smart-dial (Autodesk Fusion 360 design; units mm, degrees)
Autodesk Fusion 360 part; units mm, degrees
sketch "base outline" plane through (0, 0, 0) normal (0, 0, 1) x (1, 0, 0)
  circle A0 centre (0, 0) radius 33
  dimension "d17" = 66
  measures "d17" diameter of A0
extrude "Extrude1" add sketch "base outline" along normal blind 8.75 makes body 1
ref_plane "WorkPlane1" through (0, 0, 8.75) normal (0, 0, 1) x (1, 0, 0)
sketch "knob outline" plane through (0, 0, 8.75) normal (0, 0, 1) x (1, 0, 0)
  circle A0 centre (0, 0) radius 33
  dimension "d22" = 66
  measures "d22" diameter of A0
extrude "Extrude2" add sketch "knob outline" along normal blind 13.25 separate body makes body 2
ref_plane "WorkPlane2" through (0, 0, 22) normal (0, 0, 1) x (1, 0, 0)
sketch "knob bore" plane through (0, 0, 22) normal (0, 0, 1) x (1, 0, 0)
  circle A0 centre (0, 0) radius 28.1
  dimension "d27" = 56.2
  measures "d27" diameter of A0
extrude "Extrude3" cut sketch "knob bore" along normal mid plane 26.5 bodies 2
ref_plane "WorkPlane3" through (0, 0, 8.75) normal (0, 0, 1) x (1, 0, 0)
sketch "chassis outline" plane through (0, 0, 8.75) normal (0, 0, 1) x (1, 0, 0)
  circle A0 centre (0, 0) radius 28.1
  dimension "d32" = 56.2
  measures "d32" diameter of A0
extrude "Extrude4" add sketch "chassis outline" along normal blind 13.25 separate body makes body 3
ref_plane "WorkPlane4" through (0, 0, 22) normal (0, 0, 1) x (1, 0, 0)
sketch "glass pocket" plane through (0, 0, 22) normal (0, 0, 1) x (1, 0, 0)
  circle A0 centre (0, 0) radius 28
  dimension "d37" = 56
  measures "d37" diameter of A0
extrude "Extrude5" cut sketch "glass pocket" along normal mid plane 4 bodies 3
sketch "cover glass" plane through (0, 0, 22) normal (0, 0, 1) x (1, 0, 0)
  circle A0 centre (0, 0) radius 28
  dimension "d40" = 56
  measures "d40" diameter of A0
extrude "Extrude6" add sketch "cover glass" against normal blind 2 separate body makes body 4
sketch "active display area" plane through (0, 0, 22) normal (0, 0, 1) x (1, 0, 0)
  circle A0 centre (0, 0) radius 23.5
  dimension "d43" = 47
  measures "d43" diameter of A0
chamfer "Chamfer knob top outer" distance 0.4 distance2 0.15 1 edges at (-30.7668, -11.9333, 22) measured on face at (31.1392, -3.0355, 22) tangent chain off on bodies 2
ref_plane "WorkPlane47" through (0, 0, 7.25) normal (0, 0, 1) x (1, 0, 0)
sketch "flute sec 00" plane through (0, 0, 7.25) normal (0, 0, 1) x (1, 0, 0)
  line L0 (-3.4494, -32.8192) -> (3.4494, -32.8192)
  line L1 (3.4494, -32.8192) -> (3.4494, -38)
  line L2 (3.4494, -38) -> (-3.4494, -38)
  line L3 (-3.4494, -38) -> (-3.4494, -32.8192)
ref_plane "WorkPlane48" through (0, 0, 8.2656) normal (0, 0, 1) x (1, 0, 0)
sketch "flute sec 01" plane through (0, 0, 8.2656) normal (0, 0, 1) x (1, 0, 0)
  line L0 (-2.6582, -32.8928) -> (4.2387, -32.7267)
  line L1 (4.2387, -32.7267) -> (4.3634, -37.9059)
  line L2 (4.3634, -37.9059) -> (-2.5335, -38.072)
  line L3 (-2.5335, -38.072) -> (-2.6582, -32.8928)
ref_plane "WorkPlane49" through (0, 0, 9.2812) normal (0, 0, 1) x (1, 0, 0)
sketch "flute sec 02" plane through (0, 0, 9.2812) normal (0, 0, 1) x (1, 0, 0)
  line L0 (-1.8654, -32.9472) -> (5.0254, -32.6151)
  line L1 (5.0254, -32.6151) -> (5.2749, -37.7899)
  line L2 (5.2749, -37.7899) -> (-1.616, -38.122)
  line L3 (-1.616, -38.122) -> (-1.8654, -32.9472)
ref_plane "WorkPlane50" through (0, 0, 10.2969) normal (0, 0, 1) x (1, 0, 0)
sketch "flute sec 03" plane through (0, 0, 10.2969) normal (0, 0, 1) x (1, 0, 0)
  line L0 (-1.0716, -32.9826) -> (5.8093, -32.4846)
  line L1 (5.8093, -32.4846) -> (6.1832, -37.6519)
  line L2 (6.1832, -37.6519) -> (-0.6976, -38.1499)
  line L3 (-0.6976, -38.1499) -> (-1.0716, -32.9826)
ref_plane "WorkPlane51" through (0, 0, 11.3125) normal (0, 0, 1) x (1, 0, 0)
sketch "flute sec 04" plane through (0, 0, 11.3125) normal (0, 0, 1) x (1, 0, 0)
  line L0 (-0.2771, -32.9988) -> (6.5898, -32.3353)
  line L1 (6.5898, -32.3353) -> (7.088, -37.4921)
  line L2 (7.088, -37.4921) -> (0.2211, -38.1556)
  line L3 (0.2211, -38.1556) -> (-0.2771, -32.9988)
ref_plane "WorkPlane52" through (0, 0, 12.3281) normal (0, 0, 1) x (1, 0, 0)
sketch "flute sec 05" plane through (0, 0, 12.3281) normal (0, 0, 1) x (1, 0, 0)
  line L0 (0.5175, -32.9959) -> (7.3665, -32.1673)
  line L1 (7.3665, -32.1673) -> (7.9887, -37.3106)
  line L2 (7.9887, -37.3106) -> (1.1398, -38.1392)
  line L3 (1.1398, -38.1392) -> (0.5175, -32.9959)
ref_plane "WorkPlane53" through (0, 0, 13.3438) normal (0, 0, 1) x (1, 0, 0)
sketch "flute sec 06" plane through (0, 0, 13.3438) normal (0, 0, 1) x (1, 0, 0)
  line L0 (1.3119, -32.9739) -> (8.1389, -31.9806)
  line L1 (8.1389, -31.9806) -> (8.8848, -37.1074)
  line L2 (8.8848, -37.1074) -> (2.0578, -38.1007)
  line L3 (2.0578, -38.1007) -> (1.3119, -32.9739)
ref_plane "WorkPlane54" through (0, 0, 14.3594) normal (0, 0, 1) x (1, 0, 0)
sketch "flute sec 07" plane through (0, 0, 14.3594) normal (0, 0, 1) x (1, 0, 0)
  line L0 (2.1054, -32.9328) -> (8.9065, -31.7754)
  line L1 (8.9065, -31.7754) -> (9.7757, -36.8827)
  line L2 (9.7757, -36.8827) -> (2.9746, -38.0401)
  line L3 (2.9746, -38.0401) -> (2.1054, -32.9328)
ref_plane "WorkPlane55" through (0, 0, 15.375) normal (0, 0, 1) x (1, 0, 0)
sketch "flute sec 08" plane through (0, 0, 15.375) normal (0, 0, 1) x (1, 0, 0)
  line L0 (2.8978, -32.8725) -> (9.669, -31.5517)
  line L1 (9.669, -31.5517) -> (10.6609, -36.6366)
  line L2 (10.6609, -36.6366) -> (3.8897, -37.9575)
  line L3 (3.8897, -37.9575) -> (2.8978, -32.8725)
ref_plane "WorkPlane56" through (0, 0, 16.3906) normal (0, 0, 1) x (1, 0, 0)
sketch "flute sec 09" plane through (0, 0, 16.3906) normal (0, 0, 1) x (1, 0, 0)
  line L0 (3.6885, -32.7932) -> (10.426, -31.3097)
  line L1 (10.426, -31.3097) -> (11.54, -36.3693)
  line L2 (11.54, -36.3693) -> (4.8025, -37.8528)
  line L3 (4.8025, -37.8528) -> (3.6885, -32.7932)
ref_plane "WorkPlane57" through (0, 0, 17.4062) normal (0, 0, 1) x (1, 0, 0)
sketch "flute sec 10" plane through (0, 0, 17.4062) normal (0, 0, 1) x (1, 0, 0)
  line L0 (4.477, -32.6949) -> (11.1768, -31.0496)
  line L1 (11.1768, -31.0496) -> (12.4124, -36.0809)
  line L2 (12.4124, -36.0809) -> (5.7125, -37.7262)
  line L3 (5.7125, -37.7262) -> (4.477, -32.6949)
ref_plane "WorkPlane58" through (0, 0, 18.4219) normal (0, 0, 1) x (1, 0, 0)
sketch "flute sec 11" plane through (0, 0, 18.4219) normal (0, 0, 1) x (1, 0, 0)
  line L0 (5.2629, -32.5776) -> (11.9212, -30.7715)
  line L1 (11.9212, -30.7715) -> (13.2775, -35.7716)
  line L2 (13.2775, -35.7716) -> (6.6193, -37.5777)
  line L3 (6.6193, -37.5777) -> (5.2629, -32.5776)
ref_plane "WorkPlane59" through (0, 0, 19.4375) normal (0, 0, 1) x (1, 0, 0)
sketch "flute sec 12" plane through (0, 0, 19.4375) normal (0, 0, 1) x (1, 0, 0)
  line L0 (6.0458, -32.4415) -> (12.6587, -30.4755)
  line L1 (12.6587, -30.4755) -> (14.135, -35.4415)
  line L2 (14.135, -35.4415) -> (7.5222, -37.4074)
  line L3 (7.5222, -37.4074) -> (6.0458, -32.4415)
ref_plane "WorkPlane60" through (0, 0, 20.4531) normal (0, 0, 1) x (1, 0, 0)
sketch "flute sec 13" plane through (0, 0, 20.4531) normal (0, 0, 1) x (1, 0, 0)
  line L0 (6.8252, -32.2865) -> (13.3888, -30.1619)
  line L1 (13.3888, -30.1619) -> (14.9843, -35.0909)
  line L2 (14.9843, -35.0909) -> (8.4207, -37.2155)
  line L3 (8.4207, -37.2155) -> (6.8252, -32.2865)
ref_plane "WorkPlane61" through (0, 0, 21.4688) normal (0, 0, 1) x (1, 0, 0)
sketch "flute sec 14" plane through (0, 0, 21.4688) normal (0, 0, 1) x (1, 0, 0)
  line L0 (7.6006, -32.1128) -> (14.1112, -29.8308)
  line L1 (14.1112, -29.8308) -> (15.8249, -34.7199)
  line L2 (15.8249, -34.7199) -> (9.3143, -37.0019)
  line L3 (9.3143, -37.0019) -> (7.6006, -32.1128)
ref_plane "WorkPlane62" through (0, 0, 22.4844) normal (0, 0, 1) x (1, 0, 0)
sketch "flute sec 15" plane through (0, 0, 22.4844) normal (0, 0, 1) x (1, 0, 0)
  line L0 (8.3716, -31.9205) -> (14.8253, -29.4824)
  line L1 (14.8253, -29.4824) -> (16.6563, -34.3288)
  line L2 (16.6563, -34.3288) -> (10.2026, -36.7669)
  line L3 (10.2026, -36.7669) -> (8.3716, -31.9205)
ref_plane "WorkPlane63" through (0, 0, 23.5) normal (0, 0, 1) x (1, 0, 0)
sketch "flute sec 16" plane through (0, 0, 23.5) normal (0, 0, 1) x (1, 0, 0)
  line L0 (9.1378, -31.7096) -> (15.5309, -29.1168)
  line L1 (15.5309, -29.1168) -> (17.478, -33.9178)
  line L2 (17.478, -33.9178) -> (11.0849, -36.5106)
  line L3 (11.0849, -36.5106) -> (9.1378, -31.7096)
loft "Flute cutter" add profiles "flute sec 00", "flute sec 01", "flute sec 02", "flute sec 03", "flute sec 04", "flute sec 05", "flute sec 06", "flute sec 07", "flute sec 08", "flute sec 09", "flute sec 10", "flute sec 11", "flute sec 12", "flute sec 13", "flute sec 14", "flute sec 15", "flute sec 16" section 1 section 2 section 3 section 4 section 5 section 6 section 7 section 8 section 9 section 10 section 11 section 12 section 13 section 14 section 15 section 16 section 17 separate body makes body 5
pattern_circular "Flutes around" count 30 over 360 about axis through (0, 0, 1.75) along (0, 0, 1) of bodies 5 makes body 6 at (19.5252, -32.6204, 19.8889) makes body 7 at (25.8807, -27.848, 19.8889) makes body 8 at (31.105, -21.8586, 19.8889) makes body 9 at (34.97, -14.9138, 19.8889) makes body 10 at (37.3066, -7.3173, 19.8889) makes body 11 at (38.0127, 0.5991, 19.8889) makes body 12 at (37.6477, 5.2892, 16.2778) makes body 13 at (35.7253, 13.001, 16.2778) makes body 14 at (30.4007, 22.828, 19.8889) makes body 15 at (24.9902, 28.6498, 19.8889) makes body 16 at (18.4875, 33.2195, 19.8889) makes body 17 at (11.1768, 36.3373, 19.8889) makes body 18 at (5.6609, 37.5936, 19.8889) makes body 19 at (-4.5692, 37.7418, 19.8889) makes body 20 at (-9.1955, 36.8885, 16.2778) makes body 21 at (-19.5252, 32.6204, 19.8889) makes body 22 at (-25.8807, 27.848, 19.8889) makes body 23 at (-31.105, 21.8586, 19.8889) makes body 24 at (-34.97, 14.9138, 19.8889) makes body 25 at (-36.7959, 9.5595, 19.8889) makes body 26 at (-38.0127, -0.5991, 19.8889) makes body 27 at (-37.0574, -8.4893, 19.8889) makes body 28 at (-34.4826, -16.0085, 19.8889) makes body 29 at (-30.4007, -22.828, 19.8889) makes body 30 at (-24.9902, -28.6498, 19.8889) makes body 31 at (-18.4875, -33.2195, 19.8889) makes body 32 at (-11.1768, -36.3373, 19.8889) makes body 33 at (-3.3776, -37.8671, 19.8889) makes body 34 at (4.5692, -37.7418, 19.8889)
combine "Cut flutes" operation cut target body 2 tool bodies 5 6 7 8 9 10 11 12 13 14 15 16 17 18 19 20 21 22 23 24 25 26 27 28 29 30 31 32 33 34 5
split_face "Split screen from bezel" 1 faces at (9.2788, 5.1402, 22) by curves path "active display area" along A0 on bodies 4
ref_plane "WorkPlane69" through (0, -33, 0) normal (0, 1, 0) x (0, 0, 1)
sketch "Reset pinhole" plane through (0, -33, 0) normal (0, 1, 0) x (1, 0, 0)
  circle A0 centre (0, -4.375) radius 0.8
extrude "Extrude49" add sketch "Reset pinhole" along normal blind 4 separate body makes body 35
move_body "Move42" bodies 35 to x (0.770513, -0.637424, 0) y (0.637424, 0.770513, 0) z (0, 0, 1) at (0, 0, 0)
sketch "USB-C" plane through (0, -33, 0) normal (0, 1, 0) x (1, 0, 0)
  line L0 (-3.05, -2.725) -> (3.05, -2.725)
  line L1 (-3.05, -6.025) -> (3.05, -6.025)
  arc A0 (3.05, -6.025) -> (3.05, -2.725) centre (3.05, -4.375) ccw
  arc A1 (-3.05, -2.725) -> (-3.05, -6.025) centre (-3.05, -4.375) ccw
extrude "Extrude50" add sketch "USB-C" along normal blind 7 separate body makes body 36
move_body "Move43" bodies 36 to x (0.951057, -0.309017, 0) y (0.309017, 0.951057, 0) z (0, 0, 1) at (0, 0, 0)
sketch "Headphone jack" plane through (0, -33, 0) normal (0, 1, 0) x (1, 0, 0)
  circle A0 centre (0, -4.375) radius 2.25
extrude "Extrude51" add sketch "Headphone jack" along normal blind 3 separate body makes body 37
move_body "Move44" bodies 37 to x (0.971134, 0.238533, 0) y (-0.238533, 0.971134, 0) z (0, 0, 1) at (0, 0, 0)
sketch "Toggle switch cutout" plane through (0, -33, 0) normal (0, 1, 0) x (1, 0, 0)
  line L0 (-2.7, -2.4) -> (2.7, -2.4)
  line L1 (-2.7, -5.5) -> (2.7, -5.5)
  line L2 (3.9, -4.3) -> (3.9, -3.6)
  line L3 (-3.9, -4.3) -> (-3.9, -3.6)
  arc A0 (3.9, -3.6) -> (2.7, -2.4) centre (2.7, -3.6) ccw
  arc A1 (2.7, -5.5) -> (3.9, -4.3) centre (2.7, -4.3) ccw
  arc A2 (-3.9, -4.3) -> (-2.7, -5.5) centre (-2.7, -4.3) ccw
  arc A3 (-2.7, -2.4) -> (-3.9, -3.6) centre (-2.7, -3.6) ccw
extrude "Extrude52" add sketch "Toggle switch cutout" along normal blind 1.2 separate body makes body 38
move_body "Move45" bodies 38 to x (0.802817, 0.596225, 0) y (-0.596225, 0.802817, 0) z (0, 0, 1) at (0, 0, 0)
combine "Cut base ports" operation cut target body 1 tool bodies 35 36 37 38
sketch "USB-C tongue" plane through (0, -33, 0) normal (0, 1, 0) x (1, 0, 0)
  line L0 (-3.05, -4.025) -> (3.05, -4.025)
  line L1 (-3.05, -4.725) -> (3.05, -4.725)
  arc A0 (3.05, -4.725) -> (3.05, -4.025) centre (3.05, -4.375) ccw
  arc A1 (-3.05, -4.025) -> (-3.05, -4.725) centre (-3.05, -4.375) ccw
extrude "Extrude53" add sketch "USB-C tongue" along normal blind 5.2 from surface at 1.3 separate body makes body 39
move_body "Move46" bodies 39 to x (0.951057, -0.309017, 0) y (0.309017, 0.951057, 0) z (0, 0, 1) at (0, 0, 0)
sketch "Toggle switch" plane through (0, -33, 0) normal (0, 1, 0) x (1, 0, 0)
  line L0 (0.1, -2.5) -> (2.7, -2.5)
  line L1 (0.1, -5.4) -> (2.7, -5.4)
  line L2 (3.8, -4.3) -> (3.8, -3.6)
  line L3 (-1, -4.3) -> (-1, -3.6)
  arc A0 (3.8, -3.6) -> (2.7, -2.5) centre (2.7, -3.6) ccw
  arc A1 (2.7, -5.4) -> (3.8, -4.3) centre (2.7, -4.3) ccw
  arc A2 (-1, -4.3) -> (0.1, -5.4) centre (0.1, -4.3) ccw
  arc A3 (0.1, -2.5) -> (-1, -3.6) centre (0.1, -3.6) ccw
extrude "Extrude54" add sketch "Toggle switch" along normal blind 1.3 from surface at -0.2 separate body makes body 40
move_body "Move47" bodies 40 to x (0.802817, 0.596225, 0) y (-0.596225, 0.802817, 0) z (0, 0, 1) at (0, 0, 0)
sketch "Base rim relief" plane through (0, 0, 0) normal (0, 0, 1) x (1, 0, 0)
  circle A0 centre (0, 0) radius 31.2
  circle A1 centre (0, 0) radius 35
  dimension "d372" = 62.4
  measures "d372" diameter of A0
extrude "Base rim relief (1)" cut sketch "Base rim relief" along normal blind 1 bodies 1
equation "dia_overall = 66 mm" comment "Outer diameter - READ from Waveshare outline drawing"
equation "h_overall = 22 mm" comment "Overall height - READ from Waveshare outline drawing"
equation "h_knob = 13.25 mm" comment "Blue knob height - MEASURED BY DARREN on the real dial"
equation "h_base = h_overall - h_knob" comment "Black base height = h_overall - h_knob"
equation "dia_base = dia_overall" comment "Base diameter - DARREN: flush with the flute tips, no overhang"
equation "dia_bore = dia_glass + 2 * glass_gap" comment "Knob opening = glass plus the 0.1 mm gap each side"
equation "dia_glass = 56 mm" comment "Cover glass diameter - MEASURED BY DARREN"
equation "dia_active = 47 mm" comment "Active screen area - MEASURED BY DARREN (black border 4.5 mm wide)"
equation "glass_recess = 0 mm" comment "DARREN: glass is flush with the top, no recess"
equation "t_glass = 2 mm" comment "Glass plus bezel stack thickness - GUESS"
equation "c_knob_top = 0.4 mm" comment "Top-edge chamfer: bite across the TOP face"
equation "flute_count = 30" comment "Flutes - COUNTED BY DARREN on the real dial"
equation "flute_depth = 0.1808 mm" comment "MINIMUM possible: flat facets, flute meets flute with no gap"
equation "flute_twist = 18 deg" comment "Twist of a flute over the knob height - measured off the Waveshare render"
equation "z_ports = h_base / 2" comment "Ports sit on the vertical midline of the black base - DARREN"
equation "d17 = dia_base"
equation "d18 = h_base"
equation "d20 = h_base"
equation "d22 = dia_overall"
equation "d23 = h_knob"
equation "d25 = h_overall"
equation "d27 = dia_bore"
equation "d28 = h_knob"
equation "d30 = h_base"
equation "d32 = dia_bore"
equation "d33 = h_knob - glass_recess"
equation "d35 = h_overall - glass_recess"
equation "d37 = dia_glass"
equation "d38 = t_glass"
equation "d40 = dia_glass"
equation "d41 = -t_glass"
equation "d43 = dia_active"
equation "d212 = flute_count"
equation "glass_gap = 0.1 mm" comment "Gap between the blue ring and the glass - DARREN"
equation "c_knob_side = 0.15 mm" comment "Top-edge chamfer: drop down the SIDE face"
equation "d224 = c_knob_top"
equation "d225 = c_knob_side"
equation "toggle_w = 7.8 mm" comment "Toggle cutout width"
equation "toggle_h = 2.9 mm + 2 * toggle_gap" comment "Cutout height = 2.9 mm button (CALIPERS) plus clearance each side"
equation "toggle_corner = 1.2 mm" comment "Toggle cutout corner radius - scaled with the new height to keep the same look"
equation "toggle_gap = 0.1 mm" comment "Clearance between the toggle and its cutout - DARREN"
equation "toggle_proud = 0.2 mm" comment "How far the toggle stands out of the base - DARREN"
equation "toggle_sw = 4.8 mm" comment "Toggle button width - CALIPERS"
equation "toggle_z = toggle_from_bottom + toggle_h / 2 - z_ports" comment "Derived: puts the cutout bottom toggle_from_bottom above the base bottom"
equation "toggle_from_bottom = 2.4 mm" comment "Bottom of the toggle cutout above the bottom of the base - CALIPERS"
equation "d348 = -dia_base / 2"
equation "foot_dia = 62.4 mm" comment "Central foot that drops into the mount recess - mount side is 62.6, 0.1 clearance each side"
equation "foot_step = 1 mm" comment "How far the outer rim is relieved - matches the 1 mm step in the Smart Dial v2 mount"
equation "d372 = foot_dia"
equation "d373 = foot_step"
named bodies: "Base (black)", "Knob (blue anodised)", "Chassis / bezel (black)", "Cover glass", "cutter Reset pinhole", "cutter USB-C", "cutter Headphone jack", "cutter Toggle switch cutout", "USB-C tongue", "Toggle switch"
